Autodesk Fusion 360 part; units mm, degrees
(part 6 of 6)
equation "d10775 = fan_hole"
equation "d10776 = abs(( ( pod_w / 2 - stack_t - col_gap ) - fb_w ) + ( fb_w - fbox_t ) * 1 / 4 - fan_hp / 2)"
equation "d10777 = abs(dr_acc_face_y + clr + cart_d / 2 - fan_hp / 2)"
equation "d10778 = ( dt_zb + face_t + sof_fill_t + cart_w - blk_t - fan_t + fan_t + blk_t ) - ( dt_zb + face_t + sof_fill_t + cart_w - blk_t - fan_t + fan_t )"
equation "d10780 = dt_zb + face_t + sof_fill_t + cart_w - blk_t - fan_t + fan_t"
equation "d10782 = fan_hole"
equation "d10783 = abs(( ( pod_w / 2 - stack_t - col_gap ) - fb_w ) + ( fb_w - fbox_t ) * 1 / 4 - fan_hp / 2)"
equation "d10784 = abs(dr_acc_face_y + clr + cart_d / 2 + fan_hp / 2)"
equation "d10785 = ( dt_zb + face_t + sof_fill_t + cart_w - blk_t - fan_t + fan_t + blk_t ) - ( dt_zb + face_t + sof_fill_t + cart_w - blk_t - fan_t + fan_t )"
equation "d10787 = dt_zb + face_t + sof_fill_t + cart_w - blk_t - fan_t + fan_t"
equation "d10789 = fan_hole"
equation "d10790 = abs(( ( pod_w / 2 - stack_t - col_gap ) - fb_w ) + ( fb_w - fbox_t ) * 1 / 4 + fan_hp / 2)"
equation "d10791 = abs(dr_acc_face_y + clr + cart_d / 2 - fan_hp / 2)"
equation "d10792 = ( dt_zb + face_t + sof_fill_t + cart_w - blk_t - fan_t + fan_t + blk_t ) - ( dt_zb + face_t + sof_fill_t + cart_w - blk_t - fan_t + fan_t )"
equation "d10794 = dt_zb + face_t + sof_fill_t + cart_w - blk_t - fan_t + fan_t"
equation "d10796 = fan_hole"
equation "d10797 = abs(( ( pod_w / 2 - stack_t - col_gap ) - fb_w ) + ( fb_w - fbox_t ) * 1 / 4 + fan_hp / 2)"
equation "d10798 = abs(dr_acc_face_y + clr + cart_d / 2 + fan_hp / 2)"
equation "d10799 = ( dt_zb + face_t + sof_fill_t + cart_w - blk_t - fan_t + fan_t + blk_t ) - ( dt_zb + face_t + sof_fill_t + cart_w - blk_t - fan_t + fan_t )"
equation "d10801 = dt_zb + face_t + sof_fill_t + cart_w - blk_t - fan_t + fan_t"
equation "d10803 = fan_bore"
equation "d10804 = abs(( ( pod_w / 2 - stack_t - col_gap ) - fb_w ) + ( fb_w - fbox_t ) * 3 / 4)"
equation "d10805 = abs(dr_acc_face_y + clr + cart_d / 2)"
equation "d10806 = ( dt_zb + face_t + sof_fill_t + cart_w - blk_t - fan_t + fan_t + blk_t ) - ( dt_zb + face_t + sof_fill_t + cart_w - blk_t - fan_t + fan_t )"
equation "d10808 = dt_zb + face_t + sof_fill_t + cart_w - blk_t - fan_t + fan_t"
equation "d10810 = fan_hole"
equation "d10811 = abs(( ( pod_w / 2 - stack_t - col_gap ) - fb_w ) + ( fb_w - fbox_t ) * 3 / 4 - fan_hp / 2)"
equation "d10812 = abs(dr_acc_face_y + clr + cart_d / 2 - fan_hp / 2)"
equation "d10813 = ( dt_zb + face_t + sof_fill_t + cart_w - blk_t - fan_t + fan_t + blk_t ) - ( dt_zb + face_t + sof_fill_t + cart_w - blk_t - fan_t + fan_t )"
equation "d10815 = dt_zb + face_t + sof_fill_t + cart_w - blk_t - fan_t + fan_t"
equation "d10817 = fan_hole"
equation "d10818 = abs(( ( pod_w / 2 - stack_t - col_gap ) - fb_w ) + ( fb_w - fbox_t ) * 3 / 4 - fan_hp / 2)"
equation "d10819 = abs(dr_acc_face_y + clr + cart_d / 2 + fan_hp / 2)"
equation "d10820 = ( dt_zb + face_t + sof_fill_t + cart_w - blk_t - fan_t + fan_t + blk_t ) - ( dt_zb + face_t + sof_fill_t + cart_w - blk_t - fan_t + fan_t )"
equation "d10822 = dt_zb + face_t + sof_fill_t + cart_w - blk_t - fan_t + fan_t"
equation "d10824 = fan_hole"
equation "d10825 = abs(( ( pod_w / 2 - stack_t - col_gap ) - fb_w ) + ( fb_w - fbox_t ) * 3 / 4 + fan_hp / 2)"
equation "d10826 = abs(dr_acc_face_y + clr + cart_d / 2 - fan_hp / 2)"
equation "d10827 = ( dt_zb + face_t + sof_fill_t + cart_w - blk_t - fan_t + fan_t + blk_t ) - ( dt_zb + face_t + sof_fill_t + cart_w - blk_t - fan_t + fan_t )"
equation "d10829 = dt_zb + face_t + sof_fill_t + cart_w - blk_t - fan_t + fan_t"
equation "d10831 = fan_hole"
equation "d10832 = abs(( ( pod_w / 2 - stack_t - col_gap ) - fb_w ) + ( fb_w - fbox_t ) * 3 / 4 + fan_hp / 2)"
equation "d10833 = abs(dr_acc_face_y + clr + cart_d / 2 + fan_hp / 2)"
equation "d10834 = ( dt_zb + face_t + sof_fill_t + cart_w - blk_t - fan_t + fan_t + blk_t ) - ( dt_zb + face_t + sof_fill_t + cart_w - blk_t - fan_t + fan_t )"
equation "d10836 = rs_y0"
equation "d10838 = hole_rvn"
equation "d10839 = abs(( ( rs_x0 + dr_f08_x1 ) / 2 ))"
equation "d10840 = abs(dr_f07_zc)"
equation "d10841 = abs(( rs_y0 + rs_t ) - ( rs_y0 ))"
equation "d10843 = pod_h"
equation "d10845 = hole_rvn"
equation "d10846 = abs(slot_x0 - slv_rn_e)"
equation "d10847 = abs(slot_y0 + slv_rn_in)"
equation "d10848 = ( pod_h + slv_t ) - ( pod_h )"
equation "d10850 = pod_h + slv_t"
equation "d10852 = lock_hole"
equation "d10853 = abs(slot_x0 - slv_rn_e)"
equation "d10854 = abs(slot_y0 + slv_rn_in)"
equation "d10855 = ( pod_h + slv_t + rg_t ) - ( pod_h + slv_t )"
equation "d10857 = pod_h"
equation "d10859 = hole_rvn"
equation "d10860 = abs(slot_x0 - slv_rn_e)"
equation "d10861 = abs(slot_y0 + slot_d - slv_rn_in)"
equation "d10862 = ( pod_h + slv_t ) - ( pod_h )"
equation "d10864 = pod_h + slv_t"
equation "d10866 = lock_hole"
equation "d10867 = abs(slot_x0 - slv_rn_e)"
equation "d10868 = abs(slot_y0 + slot_d - slv_rn_in)"
equation "d10869 = ( pod_h + slv_t + rg_t ) - ( pod_h + slv_t )"
equation "d10871 = pod_h"
equation "d10873 = hole_rvn"
equation "d10874 = abs(slot_x0 + slv_rn_in)"
equation "d10875 = abs(slv_rn_yb)"
equation "d10876 = ( pod_h + slv_t ) - ( pod_h )"
equation "d10878 = pod_h + slv_t"
equation "d10880 = lock_hole"
equation "d10881 = abs(slot_x0 + slv_rn_in)"
equation "d10882 = abs(slv_rn_yb)"
equation "d10883 = ( pod_h + slv_t + rg_t ) - ( pod_h + slv_t )"
equation "d10885 = pod_h"
equation "d10887 = hole_rvn"
equation "d10888 = abs(slot_x0 + slot_w - slv_rn_in)"
equation "d10889 = abs(slv_rn_yb)"
equation "d10890 = ( pod_h + slv_t ) - ( pod_h )"
equation "d10892 = pod_h + slv_t"
equation "d10894 = lock_hole"
equation "d10895 = abs(slot_x0 + slot_w - slv_rn_in)"
equation "d10896 = abs(slv_rn_yb)"
equation "d10897 = ( pod_h + slv_t + rg_t ) - ( pod_h + slv_t )"
equation "d10899 = rs_x0"
equation "d10901 = tr_rv_d"
equation "d10902 = abs(rs_y0 + rs_d / 2 + ( -1 ) * tr_rs_py)"
equation "d10903 = abs(rs_z1 - tr_col_in / 2)"
equation "d10904 = ( rs_x0 + rs_t ) - ( rs_x0 )"
equation "d10906 = rs_x0 + rs_w - rs_t"
equation "d10908 = tr_rv_d"
equation "d10909 = abs(rs_y0 + rs_d / 2 + ( -1 ) * tr_rs_py)"
equation "d10910 = abs(rs_z1 - tr_col_in / 2)"
equation "d10911 = ( rs_x0 + rs_w ) - ( rs_x0 + rs_w - rs_t )"
equation "d10913 = rs_x0"
equation "d10915 = tr_rv_d"
equation "d10916 = abs(rs_y0 + rs_d / 2 + ( 0 ) * tr_rs_py)"
equation "d10917 = abs(rs_z1 - tr_col_in / 2)"
equation "d10918 = ( rs_x0 + rs_t ) - ( rs_x0 )"
equation "d10920 = rs_x0 + rs_w - rs_t"
equation "d10922 = tr_rv_d"
equation "d10923 = abs(rs_y0 + rs_d / 2 + ( 0 ) * tr_rs_py)"
equation "d10924 = abs(rs_z1 - tr_col_in / 2)"
equation "d10925 = ( rs_x0 + rs_w ) - ( rs_x0 + rs_w - rs_t )"
equation "d10927 = rs_x0"
equation "d10929 = tr_rv_d"
equation "d10930 = abs(rs_y0 + rs_d / 2 + ( 1 ) * tr_rs_py)"
equation "d10931 = abs(rs_z1 - tr_col_in / 2)"
equation "d10932 = ( rs_x0 + rs_t ) - ( rs_x0 )"
equation "d10934 = rs_x0 + rs_w - rs_t"
equation "d10936 = tr_rv_d"
equation "d10937 = abs(rs_y0 + rs_d / 2 + ( 1 ) * tr_rs_py)"
equation "d10938 = abs(rs_z1 - tr_col_in / 2)"
equation "d10939 = ( rs_x0 + rs_w ) - ( rs_x0 + rs_w - rs_t )"
equation "d10941 = rs_y0"
equation "d10943 = tr_rv_d"
equation "d10944 = abs(rs_x0 + tr_rs_x1)"
equation "d10945 = abs(rs_z1 - tr_col_in / 2)"
equation "d10946 = abs(( rs_y0 + rs_t ) - ( rs_y0 ))"
equation "d10948 = rs_y0 + rs_d - rs_t"
equation "d10950 = tr_rv_d"
equation "d10951 = abs(rs_x0 + tr_rs_x1)"
equation "d10952 = abs(rs_z1 - tr_col_in / 2)"
equation "d10953 = abs(( rs_y0 + rs_d ) - ( rs_y0 + rs_d - rs_t ))"
equation "d10955 = rs_y0"
equation "d10957 = tr_rv_d"
equation "d10958 = abs(rs_x0 + tr_rs_x2)"
equation "d10959 = abs(rs_z1 - tr_col_in / 2)"
equation "d10960 = abs(( rs_y0 + rs_t ) - ( rs_y0 ))"
equation "d10962 = rs_y0 + rs_d - rs_t"
equation "d10964 = tr_rv_d"
equation "d10965 = abs(rs_x0 + tr_rs_x2)"
equation "d10966 = abs(rs_z1 - tr_col_in / 2)"
equation "d10967 = abs(( rs_y0 + rs_d ) - ( rs_y0 + rs_d - rs_t ))"
equation "d10969 = sb_x0"
equation "d10971 = tr_rv_d"
equation "d10972 = abs(( -pod_d / 2 ) + sb_yf + sb_d / 2 + ( -1 ) * tr_be_py)"
equation "d10973 = abs(sb_z0 + tr_be_dz)"
equation "d10974 = ( sb_x0 + fbox_t ) - ( sb_x0 )"
equation "d10976 = sb_x0 + sb_w - fbox_t"
equation "d10978 = tr_rv_d"
equation "d10979 = abs(( -pod_d / 2 ) + sb_yf + sb_d / 2 + ( -1 ) * tr_be_py)"
equation "d10980 = abs(sb_z0 + tr_be_dz)"
equation "d10981 = ( sb_x0 + sb_w ) - ( sb_x0 + sb_w - fbox_t )"
equation "d10983 = sb_x0"
equation "d10985 = tr_rv_d"
equation "d10986 = abs(( -pod_d / 2 ) + sb_yf + sb_d / 2 + ( 0 ) * tr_be_py)"
equation "d10987 = abs(sb_z0 + tr_be_dz)"
equation "d10988 = ( sb_x0 + fbox_t ) - ( sb_x0 )"
equation "d10990 = sb_x0 + sb_w - fbox_t"
equation "d10992 = tr_rv_d"
equation "d10993 = abs(( -pod_d / 2 ) + sb_yf + sb_d / 2 + ( 0 ) * tr_be_py)"
equation "d10994 = abs(sb_z0 + tr_be_dz)"
equation "d10995 = ( sb_x0 + sb_w ) - ( sb_x0 + sb_w - fbox_t )"
equation "d10997 = sb_x0"
equation "d10999 = tr_rv_d"
equation "d11000 = abs(( -pod_d / 2 ) + sb_yf + sb_d / 2 + ( 1 ) * tr_be_py)"
equation "d11001 = abs(sb_z0 + tr_be_dz)"
equation "d11002 = ( sb_x0 + fbox_t ) - ( sb_x0 )"
equation "d11004 = sb_x0 + sb_w - fbox_t"
equation "d11006 = tr_rv_d"
equation "d11007 = abs(( -pod_d / 2 ) + sb_yf + sb_d / 2 + ( 1 ) * tr_be_py)"
equation "d11008 = abs(sb_z0 + tr_be_dz)"
equation "d11009 = ( sb_x0 + sb_w ) - ( sb_x0 + sb_w - fbox_t )"
equation "d11011 = ( -pod_d / 2 ) + sb_yf"
equation "d11013 = tr_rv_d"
equation "d11014 = abs(sb_x0 + sb_w / 2 + ( -1.5 ) * tr_bf_px)"
equation "d11015 = abs(sb_z0 + sb_h - tr_bf_dz)"
equation "d11016 = abs(( ( -pod_d / 2 ) + sb_yf + fbox_t ) - ( ( -pod_d / 2 ) + sb_yf ))"
equation "d11018 = ( -pod_d / 2 ) + sb_yf"
equation "d11020 = tr_rv_d"
equation "d11021 = abs(sb_x0 + sb_w / 2 + ( -0.5 ) * tr_bf_px)"
equation "d11022 = abs(sb_z0 + sb_h - tr_bf_dz)"
equation "d11023 = abs(( ( -pod_d / 2 ) + sb_yf + fbox_t ) - ( ( -pod_d / 2 ) + sb_yf ))"
equation "d11025 = ( -pod_d / 2 ) + sb_yf"
equation "d11027 = tr_rv_d"
equation "d11028 = abs(sb_x0 + sb_w / 2 + ( 0.5 ) * tr_bf_px)"
equation "d11029 = abs(sb_z0 + sb_h - tr_bf_dz)"
equation "d11030 = abs(( ( -pod_d / 2 ) + sb_yf + fbox_t ) - ( ( -pod_d / 2 ) + sb_yf ))"
equation "d11032 = ( -pod_d / 2 ) + sb_yf"
equation "d11034 = tr_rv_d"
equation "d11035 = abs(sb_x0 + sb_w / 2 + ( 1.5 ) * tr_bf_px)"
equation "d11036 = abs(sb_z0 + sb_h - tr_bf_dz)"
equation "d11037 = abs(( ( -pod_d / 2 ) + sb_yf + fbox_t ) - ( ( -pod_d / 2 ) + sb_yf ))"
equation "d11039 = ( -pod_d / 2 ) + sb_yf + sb_d - fbox_t"
equation "d11041 = tr_rv_d"
equation "d11042 = abs(sb_x0 + tr_bb_x0 + 0 * tr_bb_px)"
equation "d11043 = abs(sb_z0 + sb_h - tr_bb_dz)"
equation "d11044 = abs(( ( -pod_d / 2 ) + sb_yf + sb_d ) - ( ( -pod_d / 2 ) + sb_yf + sb_d - fbox_t ))"
equation "d11046 = ( -pod_d / 2 ) + sb_yf + sb_d - fbox_t"
equation "d11048 = tr_rv_d"
equation "d11049 = abs(sb_x0 + tr_bb_x0 + 1 * tr_bb_px)"
equation "d11050 = abs(sb_z0 + sb_h - tr_bb_dz)"
equation "d11051 = abs(( ( -pod_d / 2 ) + sb_yf + sb_d ) - ( ( -pod_d / 2 ) + sb_yf + sb_d - fbox_t ))"
equation "d11053 = ( -pod_d / 2 ) + sb_yf + sb_d - fbox_t"
equation "d11055 = tr_rv_d"
equation "d11056 = abs(sb_x0 + tr_bb_x0 + 2 * tr_bb_px)"
equation "d11057 = abs(sb_z0 + sb_h - tr_bb_dz)"
equation "d11058 = abs(( ( -pod_d / 2 ) + sb_yf + sb_d ) - ( ( -pod_d / 2 ) + sb_yf + sb_d - fbox_t ))"
equation "d11060 = ( -pod_d / 2 ) + sb_yf + sb_d - fbox_t"
equation "d11062 = tr_rv_d"
equation "d11063 = abs(sb_x0 + tr_bb_x0 + 3 * tr_bb_px)"
equation "d11064 = abs(sb_z0 + sb_h - tr_bb_dz)"
equation "d11065 = abs(( ( -pod_d / 2 ) + sb_yf + sb_d ) - ( ( -pod_d / 2 ) + sb_yf + sb_d - fbox_t ))"
named bodies: "COLUMN FOOT PLATE", "COLUMN FACE FRONT", "COLUMN FACE LEFT", "COLUMN PLENUM PLATE LOW", "COLUMN PLENUM PLATE HIGH", "COLUMN FILL FRONT", "COLUMN FILL LEFT", "KICK GRILLE FRONT", "KICK GRILLE LEFT", "SENSOR HUB ZONE", "COLUMN ANGLE FRONT", "COLUMN ANGLE BL", "CARTRIDGE SUPPLY", "LAYER 50 SUPPLY", "SOFFIT UNDERSIDE LEFT", "SOFFIT UNDERSIDE RIGHT", "SOFFIT UNDERSIDE FIXED", "SOFFIT FACE FRONT", "SOFFIT RAIL DOOR", "SOFFIT RAIL ROOM", "SOFFIT DOOR PLATE", "SOFFIT END PLATE LEFT", "SOFFIT FILL UNDER", "SOFFIT FILL FRONT", "EXHAUST GRILLE", "HANGER STUD", "HINGE ENVELOPE", "LATCH ENVELOPE", "LOCK SCREW", "CARTRIDGE EXHAUST", "LAYER 50 EXHAUST", "EXHAUST FAN BOX", "FAN BOX BULKHEAD EXHAUST", "FAN BOX LINING EXHAUST SIDE", "FAN BOX LINING EXHAUST FAR END", "FAN 140 ENVELOPE", "SUPPLY FAN BOX", "FAN BOX BULKHEAD SUPPLY", "FAN BOX LINING SUPPLY END", "FAN BOX LIP ANGLE SUPPLY", "FAN BOX PAD", "RISER BUFFER", "SUPPLY TRANSITION", "INTAKE RISER", "RISER TRANSITION", "ROOF SLEEVE", "ROOF GRILLE"
